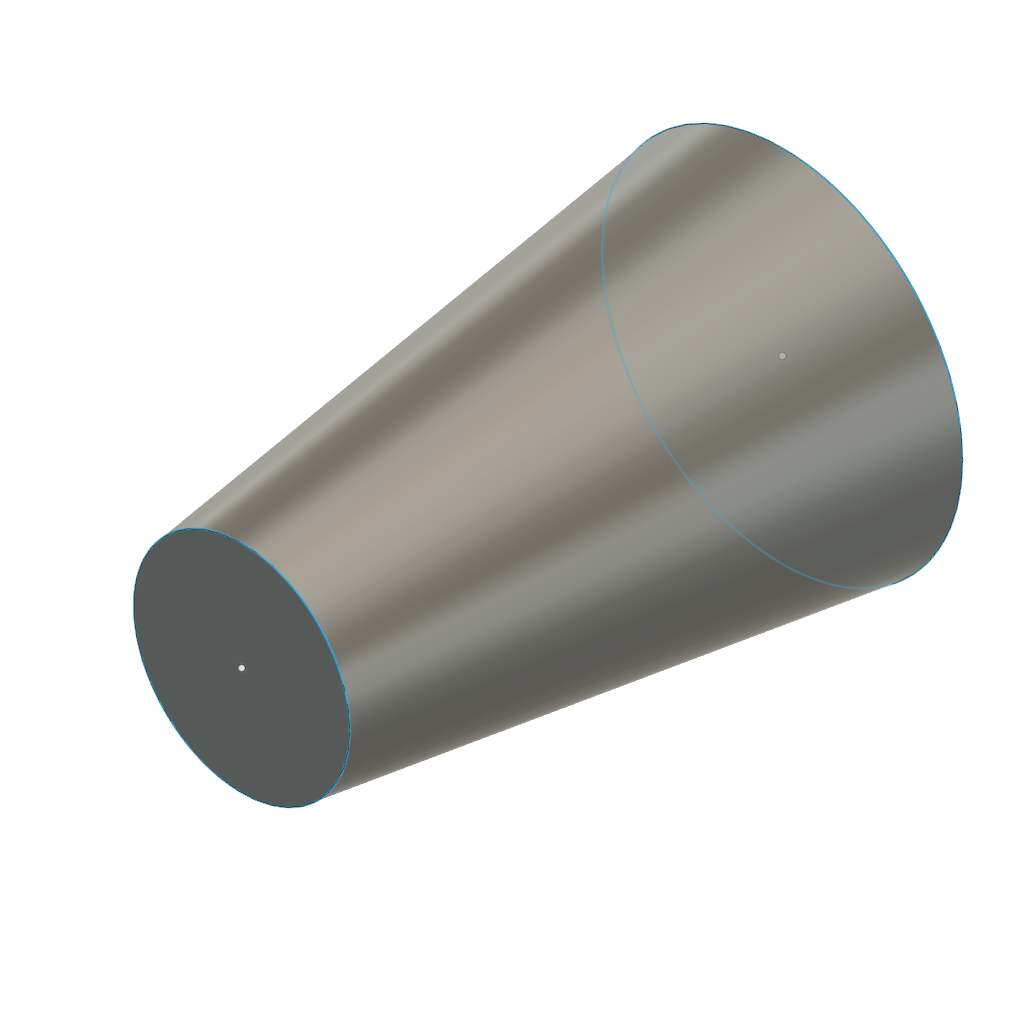
solid_two (Autodesk Fusion 360 design; units mm, degrees)
part number: 2026-10-20-21-03-44-711
Autodesk Fusion 360 part; units mm, degrees
sketch "LoftSection1" plane through (0, 0, 0) normal (0, 0, 1) x (1, 0, 0)
  circle A0 centre (0, 0) radius 10
ref_plane "WorkPlane1" through (0, 0, 30) normal (0, 0, 1) x (1, 0, 0)
sketch "LoftSection2" plane through (0, 0, 30) normal (0, 0, 1) x (1, 0, 0)
  circle A0 centre (0, 0) radius 6
loft "ProbeLoft" add profiles "LoftSection1", "LoftSection2" section 1 section 2
